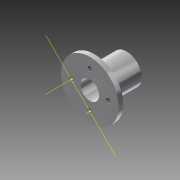
# Autodesk Inventor part: End_Mount
Saved by Autodesk Inventor 2013 (Build 170138000, 138)
## iProperties
Created: 2013-09-27
Part Number: End_Mount
Material: Generic
Document SubType Name: Modeling
Designer: Hunter
Density: 1 g/cm^3
Author: Hunter
Autodesk Inventor part; units mm, degrees
ref_plane "YZ Plane" through (0, 0, 0) normal (1, 0, 0) x (0, 1, 0)
ref_plane "XZ Plane" through (0, 0, 0) normal (0, 1, 0) x (-1, 0, 0)
ref_plane "XY Plane" through (0, 0, 0) normal (0, 0, 1) x (1, 0, 0)
sketch "Sketch1" plane through (0, 0, 0) normal (0, 1, 0) x (-1, 0, 0)
  circle A0 centre (0, 0) radius 12.5
  line L0 (0, -8.3231) -> (0, 8.757)
  line L1 (-7.7314, 0) -> (5.9958, 0)
  circle A1 centre (8, 0) radius 1
  circle A2 centre (0, 8) radius 1
  circle A3 centre (-8, 0) radius 1
  circle A4 centre (0, -8) radius 1
  circle A5 centre (0, 0) radius 4
  dimension "d0" = 25
  dimension "d1" = 2
  dimension "d4" = 360
  dimension "d6" = 8
  dimension "d74" = 16
  constraints: 6 centre point, 4 coincident, 4 end point, 2 vertical, 1 horizontal, 1 perpendicular, 11 other
  measures "d0" diameter of A0
  measures "d1" diameter of A1
  measures "d6" diameter of A5
  measures "d74" distance of A1.centre A3.centre
extrude "Extrusion1" add sketch "Sketch1" along normal blind 2
sketch "Sketch2" plane through (0, 2, 0) normal (0, 1, 0) x (1, 0, 0)
  circle A0 centre (0, 0) radius 12.5 projected
  circle A1 centre (0, 0) radius 6.5
  dimension "d10" = 13
  constraints: 1 centre point, 1 coincident
  measures "d10" diameter of A1
extrude "Extrusion2" add sketch "Sketch2" along normal blind 6 contours A1
hole "Hole1" at (0, 2, 0) direction (0, 1, 0) diameter 8 depth 4
hole "Hole2" at (0, 0, -8) direction (0, 1, 0) diameter 2.013 end through all thread size "M2.5x0.45" class "6H" standard "ANSI Metric M Profile"
hole "Hole3" at (8, 0, 0) direction (0, 1, 0) diameter 2.013 end through all thread size "M2.5x0.45" class "6H" standard "ANSI Metric M Profile"
hole "Hole4" at (0, 0, 8) direction (0, 1, 0) diameter 2.013 end through all thread size "M2.5x0.45" class "6H" standard "ANSI Metric M Profile"
hole "Hole5" at (-8, 0, 0) direction (0, 1, 0) diameter 2.013 end through all thread size "M2.5x0.45" class "6H" standard "ANSI Metric M Profile"
chamfer "Chamfer1" distance 0.1 angle 45 4 edges at (0, 0, 9.0065) (8, 0, 1.0065) (-8, 0, 1.0065) (0, 0, -6.9935)
hole "Hole6" at (0, 8, 0) direction (0, -1, 0) diameter 3.17 end through all
move faces "Move Face1" translate (0, 8, 0) faces at (4.7949, 8, 0.5822)
body "Solid1"
